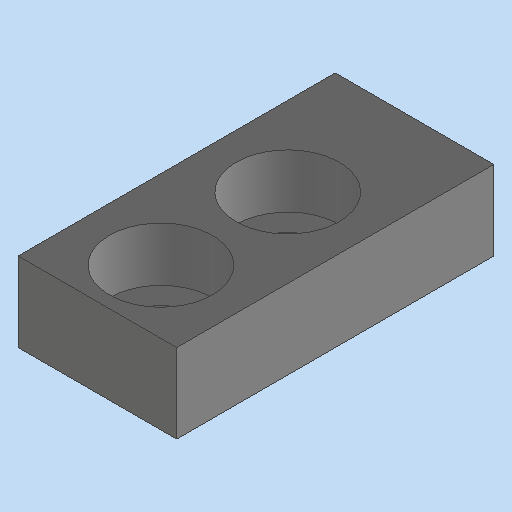
# Autodesk Inventor part: MM0937AN100_G16_156
Saved by Autodesk Inventor 2023.3 (Build 273359000, 359)
## iProperties
Created: 2024-03-15
Part Number: MM0937AN100_G16_156
Material: 1.2379 X155CrVMo12-1
Description: =<RBPARTNOTITLE2>
Document SubType Name: Modeling
Designer: FSM9BW
Mass: 5.85062 g
Surface Area: 8.36722 cm^2
Volume: 0.745302 cm^3
Density: 7.85 g/cm^3
Appearance: Stahl - rostfrei AnP
RBPARTMADEOF: 5 x 20 x 10 (FM)
RBDRAWINGMISSINGSPEC: --
AnP_Kategorie: 1
RBPARTNOTITLE2: Anfertigungsteil
RBSURFACE: plasma nitrided 1000 HV, Nht 0,1 + 0,1
RBPARTNOTITLE1: manufactured part
RBSURFACE2: plasmanitriert 1000 HV, Nht 0,1 + 0,1
AnP_Material: =<Material>
RBMATERIAL: =<Material>
RBMATNO: =<Part Number>
RBPARTNO: SIEHE MNR
MaxAbmaße: 5 x 20 x 10 (FM)
Author: FSM9BW
Keywords: =<RBPARTMADEOF>
Comments: =<RBSURFACE2>
Revision Number: 01
Autodesk Inventor part; units mm, degrees
ref_plane "YZ Plane" through (0, 0, 0) normal (1, 0, 0) x (0, 1, 0)
ref_plane "XZ Plane" through (0, 0, 0) normal (0, 1, 0) x (-1, 0, 0)
ref_plane "XY Plane" through (0, 0, 0) normal (0, 0, 1) x (1, 0, 0)
sketch "Skizze1" plane through (0, 0, 0) normal (0, 0, 1) x (1, 0, 0)
  line L0 (-5, 0) -> (5, 0)
  line L1 (5, 0) -> (5, 20)
  line L2 (5, 20) -> (-5, 20)
  line L3 (-5, 20) -> (-5, 0)
  line L4 (-7, 0) -> (7, 0) projected
  line L5 (0, -4) -> (0, 24) projected
  point P0 (0, 0)
  dimension "d0" = 10
  dimension "d1" = 20
  constraints: 8 end point, 2 parallel, 1 collinear, 1 horizontal, 1 perpendicular, 1 other
  measures "d0" distance of L0.start L0.end
  measures "d1" distance of L2.end L0.start
extrude "Extrusion1" add sketch "Skizze1" along normal blind 5
sketch "Skizze2" plane through (0, 0, 5) normal (0, 0, 1) x (1, 0, 0)
  line L0 (-5, 0) -> (5, 0) projected
  point P0 (0, 0)
  point P1 (0, 4)
  point P2 (0, 12)
  point P3 (0, 0)
  point P4 (0, 0)
  dimension "d4" = 4
  dimension "d5" = 8
  constraints: 2 midpoint, 2 vertical alignment
  measures "d4" distance from line of point (0, 4) L0
  measures "d5" distance of point (0, 12) point (0, 4)
hole "Bohrung1" at (0, 4, 5) at (0, 12, 5) direction (0, 0, -1) diameter 3.4 end through all counterbore diameter 6.5 counterbore depth 3.4 clearance for "Inbusschraube ISO 4762  versenkt" size "M3" standard "ISO"
